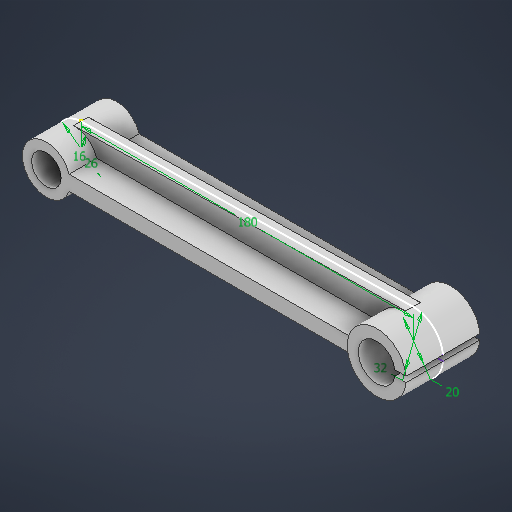
# Autodesk Inventor part: Peça6
Saved by Autodesk Inventor 2026.2 (Build 302298000, 298)
## iProperties
Created: 2026-08-07
Part Number: Peça6
Material: Genérico
Document SubType Name: Modeling
Designer: IFSP
Density: 1 g/cm^3
Appearance: Padrão
Author: IFSP
Autodesk Inventor part; units mm, degrees
ref_plane "YZ Plane" through (0, 0, 0) normal (1, 0, 0) x (0, 1, 0)
ref_plane "XZ Plane" through (0, 0, 0) normal (0, 1, 0) x (-1, 0, 0)
ref_plane "XY Plane" through (0, 0, 0) normal (0, 0, 1) x (1, 0, 0)
sketch "Esboço1" plane through (0, 0, 0) normal (0, 0, 1) x (1, 0, 0)
  circle A0 centre (0, 0) radius 13
  circle A1 centre (0, 0) radius 8
  line L0 (0, 0) -> (180, 0)
  arc A2 (189.8869, 1.5) -> (189.8869, -1.5) centre (180, 0) ccw
  arc A3 (195.9295, 1.5) -> (195.9295, -1.5) centre (180, 0) ccw
  line L1 (-0.2167, 12.9982) -> (179.7333, 15.9978)
  line L2 (-0.2167, -12.9982) -> (179.7333, -15.9978)
  line L3 (189.8869, -1.5) -> (195.9295, -1.5)
  line L4 (195.9295, 1.5) -> (189.8869, 1.5)
  line L5 (189.8869, 1.5) -> (195.9295, 1.5)
  line L6 (13.8391, -4) -> (12.3693, -4)
  line L7 (13.8391, 4) -> (12.3693, 4)
  line L8 (13.8391, -4) -> (164.5081, -4)
  line L9 (13.8391, 4) -> (164.5081, 4)
  dimension "d0" = 26
  dimension "d1" = 16
  dimension "d2" = 180
  dimension "d3" = 20
  dimension "d4" = 32
  constraints: 20 end point, 12 point on circle, 4 centre point, 4 coincident, 4 tangent, 2 horizontal, 1 collinear, 1 parallel
  measures "d0" diameter of A0
  measures "d1" diameter of A1
  measures "d2" distance of L0.start L0.end
  measures "d3" diameter of A2
  measures "d4" diameter of A3
extrude "Extrusão1" add sketch "Esboço1" along normal mid plane 8
extrude "Extrusão2" add sketch "Esboço1" along normal mid plane 20 contours A3 L4 A2 L0 | L0 A2 L3 A3
extrude "Extrusão3" add sketch "Esboço1" along normal mid plane 19 contours A0
sketch "Esboço2" plane through (-0.2167, 12.9982, 4) normal (-0.0166667, 0.9998611, 0) x (0.9998611, 0.0166667, 0)
  point P0 (0, 4)
extrude "Extrusão4" add sketch "Esboço1" along normal mid plane 38 contours A0
extrude "Extrusão5" add sketch "Esboço1" along normal mid plane 40 contours A3 L4 A2 L0 | L0 A2 L3 A3
sketch "Esboço3" plane through (0, 0, -4) normal (0, 0, -1) x (-1, 0, 0)
  point P0 (0, 0)
extrude "Extrusão6" add sketch "Esboço1" along normal mid plane 16 contours L0 A3 L8 L6 A0 | A0 L7 L9 A3 L0
extrude "Extrusão7" add sketch "Esboço1" along normal mid plane 38 contours L0 A3 L8 L6 A0 | A0 L7 L9 A3 L0
chamfer "Chanfro1" distance 1 angle 45 1 edges at (164, 0, -19)
